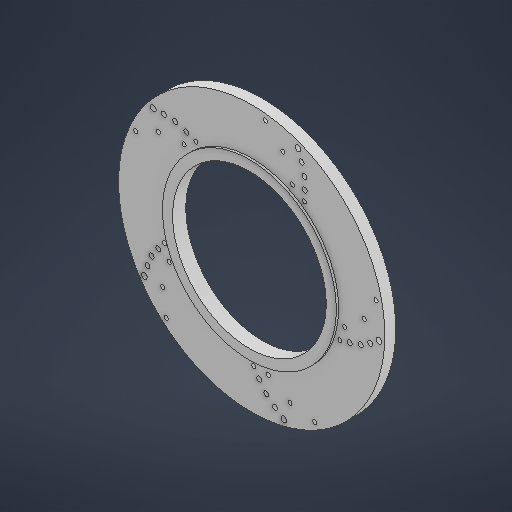
# Autodesk Inventor part: disc3 back face side
Saved by Autodesk Inventor 2027 (Build 310192060, 192F)
## iProperties
Created: 2026-07-10
Part Number: disc3 back face side
Material: Generic
Document SubType Name: Modeling
Designer: ElieH
Density: 1 g/cm^3
Appearance: Default
Author: ElieH
Autodesk Inventor part; units mm, degrees
ref_plane "YZ Plane" through (0, 0, 0) normal (1, 0, 0) x (0, 1, 0)
ref_plane "XZ Plane" through (0, 0, 0) normal (0, 1, 0) x (-1, 0, 0)
ref_plane "XY Plane" through (0, 0, 0) normal (0, 0, 1) x (1, 0, 0)
sketch "Sketch1" plane through (0, 0, 0) normal (0, 0, 1) x (1, 0, 0)
  circle A0 centre (0.1504, 0.1254) radius 145.0085
  circle A1 centre (0.1504, 0.1254) radius 94.6473
  circle A2 centre (-94.7182, -32.9655) radius 2.2011
  circle A3 centre (-101.6131, -41.6396) radius 2.6413
  circle A4 centre (-89.9318, -48.1732) radius 2.2011
  circle A5 centre (-108.9005, -52.0268) radius 2.6413
  circle A6 centre (-113.4145, -63.5262) radius 2.6413
  circle A7 centre (-116.8375, -74.6788) radius 3.0815
  circle A8 centre (-96.659, -75.259) radius 2.2011
  circle A9 centre (-92.9007, -102.5032) radius 2.2011
  circle A10 centre (0.1504, 0.1254) radius 83.6422
  circle A11 centre (8.4246, -109.5636) radius 2.6413
  circle A12 centre (16.0515, -119.7041) radius 2.6413
  circle A13 centre (25.5931, -127.5508) radius 2.6413
  circle A14 centre (35.1422, -134.2526) radius 3.0815
  circle A15 centre (18.2481, -100.473) radius 2.2011
  circle A16 centre (2.3057, -100.3257) radius 2.2011
  circle A17 centre (41.9295, -115.2409) radius 2.2011
  circle A18 centre (69.0016, -120.0855) radius 2.2011
  circle A19 centre (107.0277, -25.9012) radius 2.6413
  circle A20 centre (119.0288, -21.7811) radius 2.6413
  circle A21 centre (129.4399, -15.1313) radius 2.6413
  circle A22 centre (138.7645, -8.1206) radius 3.0815
  circle A23 centre (101.4177, -13.7493) radius 2.2011
  circle A24 centre (96.3511, -28.8659) radius 2.2011
  circle A25 centre (122.7807, 4.2095) radius 2.2011
  circle A26 centre (135.754, 28.4595) radius 2.2011
  circle A27 centre (57.9301, 93.729) radius 2.6413
  circle A28 centre (57.7202, 106.4159) radius 2.6413
  circle A29 centre (54.613, 118.3724) radius 2.6413
  circle A30 centre (50.8269, 129.407) radius 3.0815
  circle A31 centre (44.6394, 92.1487) radius 2.2011
  circle A32 centre (57.4504, 82.6588) radius 2.2011
  circle A33 centre (34.1611, 118.0158) radius 2.2011
  circle A34 centre (15.1068, 137.8477) radius 2.2011
  circle A35 centre (-71.0171, 84.0022) radius 2.6413
  circle A36 centre (-83.1478, 87.723) radius 2.6413
  circle A37 centre (-95.4793, 88.4627) radius 2.6413
  circle A38 centre (-107.1439, 88.2718) radius 3.0815
  circle A39 centre (-73.6211, 70.8736) radius 2.2011
  circle A40 centre (-60.6369, 80.1251) radius 2.2011
  circle A41 centre (-101.4601, 68.9015) radius 2.2011
  circle A42 centre (-126.2095, 56.9083) radius 2.2011
  point P0 (0, 0)
  point P1 (0.351, 0.0501)
  dimension "d2" = 167.2844
  dimension "d3" = 360
  constraints: 43 centre point, 1 coincident, 81 other
  measures "d2" diameter of A10
extrude "Extrusion1" add sketch "Sketch1" along normal blind 11.875 contours A0
extrude "Extrusion2" add sketch "Sketch1" along normal blind 14.375 contours A1
body "Solid1"
